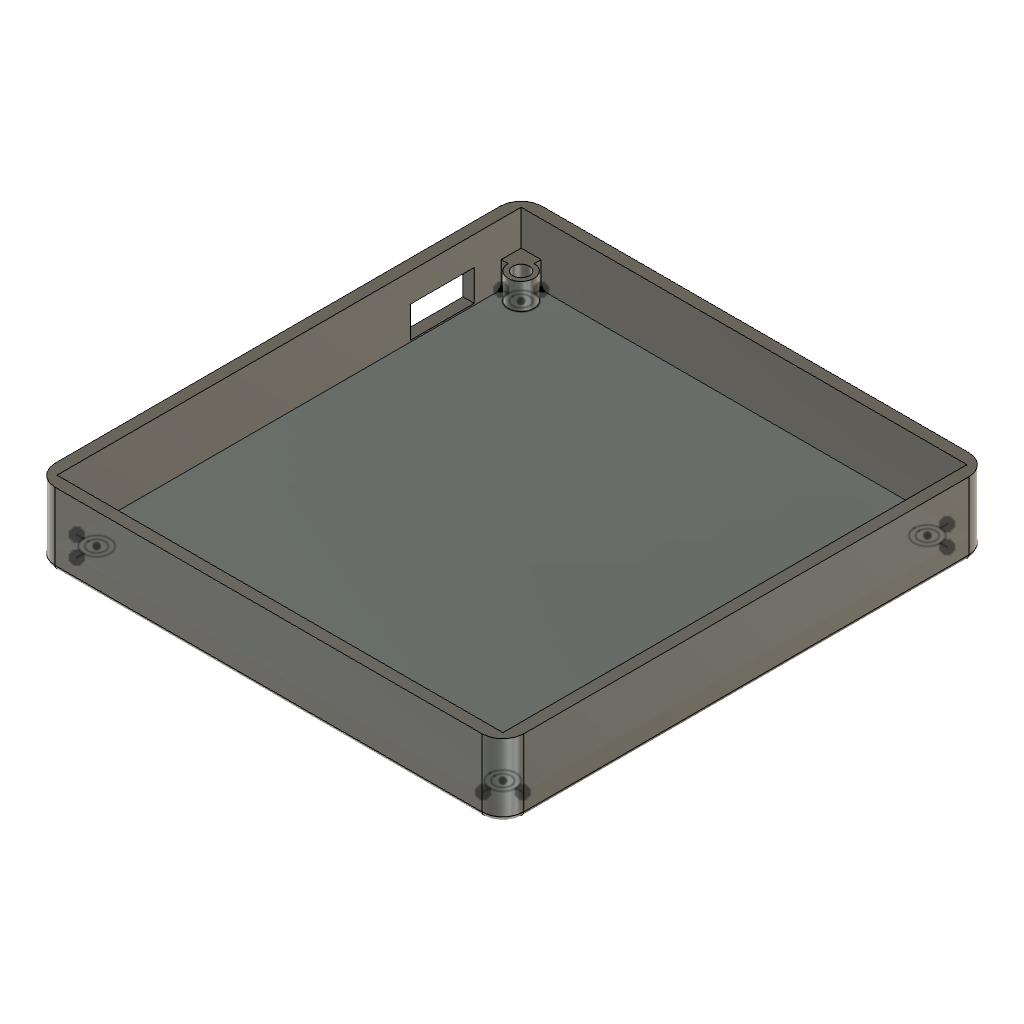
Bottom Plate 2 (Autodesk Fusion 360 design; units mm, degrees)
part number: 2026-07-24-21-20-19-494
Autodesk Fusion 360 part; units mm, degrees
sketch "Sketch1" plane through (0, 0, 0) normal (0, 0, 1) x (1, 0, 0)
  line L0 (68.6248, -31.429) -> (-21.3752, -31.429)
  line L1 (-21.3752, -31.429) -> (-21.3752, 62.071)
  line L2 (-21.3752, 62.071) -> (68.6248, 62.071)
  line L3 (68.6248, 62.071) -> (68.6248, -31.429)
  dimension "d4" = 93.5
  dimension "d5" = 90
  measures "d4" distance of L0.end L1.end
  measures "d5" distance of L1.end L2.end
extrude "Extrude1" add sketch "Sketch1" along normal blind 14
shell "Shell1" thickness 2.2 removed faces 1 at (38.6248, -0.2623, 14)
sketch "Sketch2" plane through (0, 0, 2.2) normal (0, 0, 1) x (-1, 0, 0)
  line L0 (-66.4248, -59.871) -> (19.1752, -59.871)
  line L1 (19.1752, -59.871) -> (19.1752, 29.229)
  line L2 (19.1752, 29.229) -> (-66.4248, 29.229)
  line L3 (-66.4248, 29.229) -> (-66.4248, -59.871)
  circle A0 centre (-62.6248, -56.071) radius 1.6
  circle A1 centre (-62.6248, -56.071) radius 2.5
  circle A2 centre (15.3752, -56.071) radius 1.6
  circle A3 centre (15.3752, 25.429) radius 1.6
  circle A4 centre (-62.6248, 25.429) radius 1.6
  circle A5 centre (-62.6248, 25.429) radius 2.5
  circle A6 centre (15.3752, 25.429) radius 2.5
  circle A7 centre (15.3752, -56.071) radius 2.5
  line L4 (-65.1248, -56.071) -> (-66.4248, -56.071)
  line L5 (-62.6215, -58.571) -> (-62.6215, -59.871)
  line L6 (15.3354, -58.5707) -> (15.3354, -59.871)
  line L7 (17.8752, -56.0668) -> (19.1752, -56.0668)
  line L8 (15.3724, 27.929) -> (15.3724, 29.229)
  line L9 (17.8752, 25.429) -> (19.1752, 25.429)
  line L10 (-62.6248, 27.929) -> (-62.6248, 29.229)
  line L11 (-65.1248, 25.429) -> (-66.4248, 25.429)
  dimension "d9" = 3.2
  dimension "d10" = 3.8
  dimension "d11" = 3.8
  dimension "d12" = 5
  dimension "d13" = 3.2
  dimension "d14" = 3.8
  dimension "d15" = 3.8
  dimension "d16" = 3.2
  dimension "d17" = 3.8
  dimension "d18" = 3.8
  dimension "d19" = 3.2
  dimension "d20" = 3.8
  dimension "d21" = 3.8
  dimension "d22" = 5
  dimension "d23" = 5
  dimension "d24" = 5
  dimension "d25" = 1.3
  dimension "d26" = 1.3
  dimension "d27" = 1.3003
  dimension "d28" = 1.3
  dimension "d29" = 1.3
  dimension "d30" = 1.3
  dimension "d31" = 1.3
  dimension "d32" = 1.3
  constraint concentric A0 A1
  constraint concentric A4 A5
  constraint concentric A3 A6
  constraint concentric A2 A7
  constraint coincident A1 L4.start
  constraint coincident L3 L4.end
  constraint perpendicular L3 L4
  constraint coincident A1 L5.start
  constraint coincident L0 L5.end
  constraint perpendicular L0 L5
  constraint coincident A7 L6.start
  constraint coincident L0 L6.end
  constraint perpendicular L0 L6
  constraint coincident A7 L7.start
  constraint coincident L1 L7.end
  constraint perpendicular L1 L7
  constraint coincident A6 L8.start
  constraint coincident L2 L8.end
  constraint perpendicular L2 L8
  constraint coincident A6 L9.start
  constraint coincident L1 L9.end
  constraint perpendicular L1 L9
  constraint coincident A5 L10.start
  constraint coincident L2 L10.end
  constraint perpendicular L2 L10
  constraint coincident A5 L11.start
  constraint coincident L3 L11.end
  constraint perpendicular L3 L11
  measures "d9" diameter of A0
  measures "d10" distance of L0 A0.centre
  measures "d11" distance of L3 A0.centre
  measures "d12" diameter of A1
  measures "d13" diameter of A2
  measures "d14" distance of L0 A2.centre
  measures "d15" distance of L1 A2.centre
  measures "d16" diameter of A3
  measures "d17" distance of L2 A3.centre
  measures "d18" distance of L1 A3.centre
  measures "d19" diameter of A4
  measures "d20" distance of L3 A4.centre
  measures "d21" distance of L2 A4.centre
  measures "d22" diameter of A5
  measures "d23" diameter of A6
  measures "d24" diameter of A7
  measures "d25" distance of L4.start L4.end
  measures "d26" distance of L5.start L5.end
  measures "d27" distance of L6.start L6.end
  measures "d28" distance of L7.start L7.end
  measures "d29" distance of L8.start L8.end
  measures "d30" distance of L9.start L9.end
  measures "d31" distance of L10.start L10.end
  measures "d32" distance of L11.start L11.end
extrude "Extrude2" add sketch "Sketch2" along normal blind 5 contours L0 L3 A1 L4 L5 | A1
extrude "Extrude3" add sketch "Sketch2" along normal blind 5 contours L0 L1 A7 L6 L7 | A7
extrude "Extrude4" add sketch "Sketch2" along normal blind 5 contours L1 L2 A6 L8 L9 | A6
extrude "Extrude5" add sketch "Sketch2" along normal blind 5 contours L2 L3 A5 L10 L11 | A5
fillet "Fillet1" radius 4 4 edges at (-21.3752, -31.429, 7) (68.6248, -31.429, 7) (68.6248, 62.071, 7) (-21.3752, 62.071, 7)
fillet "Fillet2" radius 1 8 edges at (67.4532, 60.8995, 0) (68.6248, 15.321, 0) (67.4532, -30.2574, 0) (23.6248, -31.429, 0) (-20.2036, -30.2574, 0) (-21.3752, 15.321, 0) (-20.2036, 60.8995, 0) (23.6248, 62.071, 0)
sketch "Sketch3" plane through (-21.3752, 0, 0) normal (-1, 0, 0) x (0, -1, 0)
  line L0 (-58.071, 1) -> (27.429, 1)
  line L1 (27.429, 1) -> (27.429, 14)
  line L2 (27.429, 14) -> (-58.071, 14)
  line L3 (-58.071, 14) -> (-58.071, 1)
  line L4 (-50.8784, 8.4841) -> (-38.6184, 8.4841)
  line L5 (-38.6184, 8.4841) -> (-38.6184, 2.5041)
  line L6 (-38.6184, 2.5041) -> (-50.8784, 2.5041)
  line L7 (-50.8784, 2.5041) -> (-50.8784, 8.4841)
  dimension "d45" = 12.26
  dimension "d46" = 5.98
  constraint horizontal L4
  constraint vertical L5
  constraint horizontal L6
  constraint vertical L7
  measures "d45" distance of L4.start L4.end
  measures "d46" distance of L4.end L5.end
extrude "Extrude6" cut sketch "Sketch3" against normal blind 20 contours L4 L5 L6 L7
